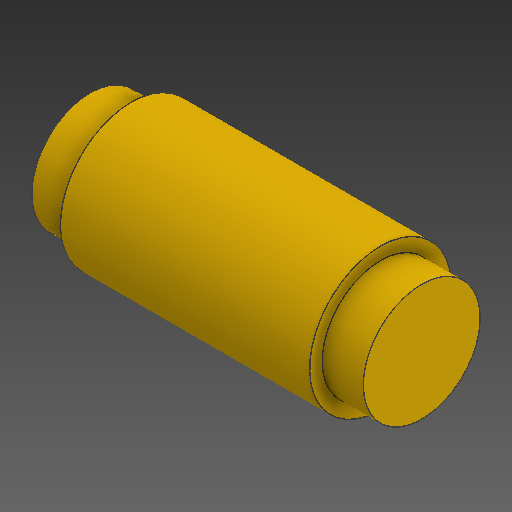
# Autodesk Inventor part: Eje de cojinetes
Saved by Autodesk Inventor 2026.1 (Build 301233020, 233B)
## iProperties
Created: 2026-10-19
Part Number: Eje de cojinetes
Material: Generic
Document SubType Name: Sheet Metal
Designer: YmCris
Density: 1 g/cm^3
Sheet Metal Rule: Default_mm
Appearance: Default
Author: YmCris
Autodesk Inventor part; units mm, degrees
ref_plane "YZ Plane" through (0, 0, 0) normal (1, 0, 0) x (0, 1, 0)
ref_plane "XZ Plane" through (0, 0, 0) normal (0, 1, 0) x (-1, 0, 0)
ref_plane "XY Plane" through (0, 0, 0) normal (0, 0, 1) x (1, 0, 0)
sketch "Sketch1" plane through (0, 0, 0) normal (0, 0, 1) x (1, 0, 0)
  line L0 (0, 28.45) -> (50, 28.45)
  line L1 (50, 28.45) -> (50, 23.45)
  line L2 (50, 23.45) -> (66.5, 23.45)
  line L3 (66.5, 23.45) -> (66.5, 0)
  line L4 (66.5, 0) -> (0, 0)
  line L5 (0, 28.45) -> (-50, 28.45)
  line L6 (-50, 28.45) -> (-50, 23.45)
  line L7 (-50, 23.45) -> (-66.5, 23.45)
  line L8 (-66.5, 23.45) -> (-66.5, 0)
  line L9 (-66.5, 0) -> (0, 0)
  line L10 (-93.1, 0) -> (93.1, 0) projected
  point P0 (-109.06, 0)
  point P1 (95.76, 0)
  point P2 (-66.5, 11.725)
  point P3 (-50, 25.95)
  point P4 (50, 25.95)
  dimension "d1" = 50
  dimension "d2" = 5
  dimension "d3" = 16.5
  dimension "d4" = 23.45
  dimension "d7" = 133
  dimension "d8" = 100
  dimension "d9" = 16.5
  constraints: 20 end point, 3 midpoint, 3 perpendicular, 2 coincident
  measures "d1" distance of L0.start L0.end
  measures "d2" distance of L0.end L1.end
  measures "d3" distance of L1.end L2.end
  measures "d4" distance of L2.end L3.end
  measures "d7" distance from line of point (-66.5, 11.725) L3
  measures "d8" distance of point (-50, 25.95) point (50, 25.95)
  measures "d9" horizontal distance of L7.end L5.end
revolve "Revolution2" add sketch "Sketch1" angle 360 about axis through (-10, 0, 0) along (1, 0, 0)
equation "\"BendRadius\" = Thickness"
equation "\"BendReliefWidth\" = Thickness"
equation "\"BendReliefDepth\" = 0.5 * Thickness"
equation "\"CornerReliefSize\" = 4 * Thickness"
equation "\"MinimumRemnant\" = 2 * Thickness"
equation "\"TransitionRadius\" = BendRadius"
equation "\"JacobiRadiusSize\" = BendRadius"
equation "\"GapSize\" = Thickness"
equation "\"Thickness\" = 46.9"
body "Solid2"
